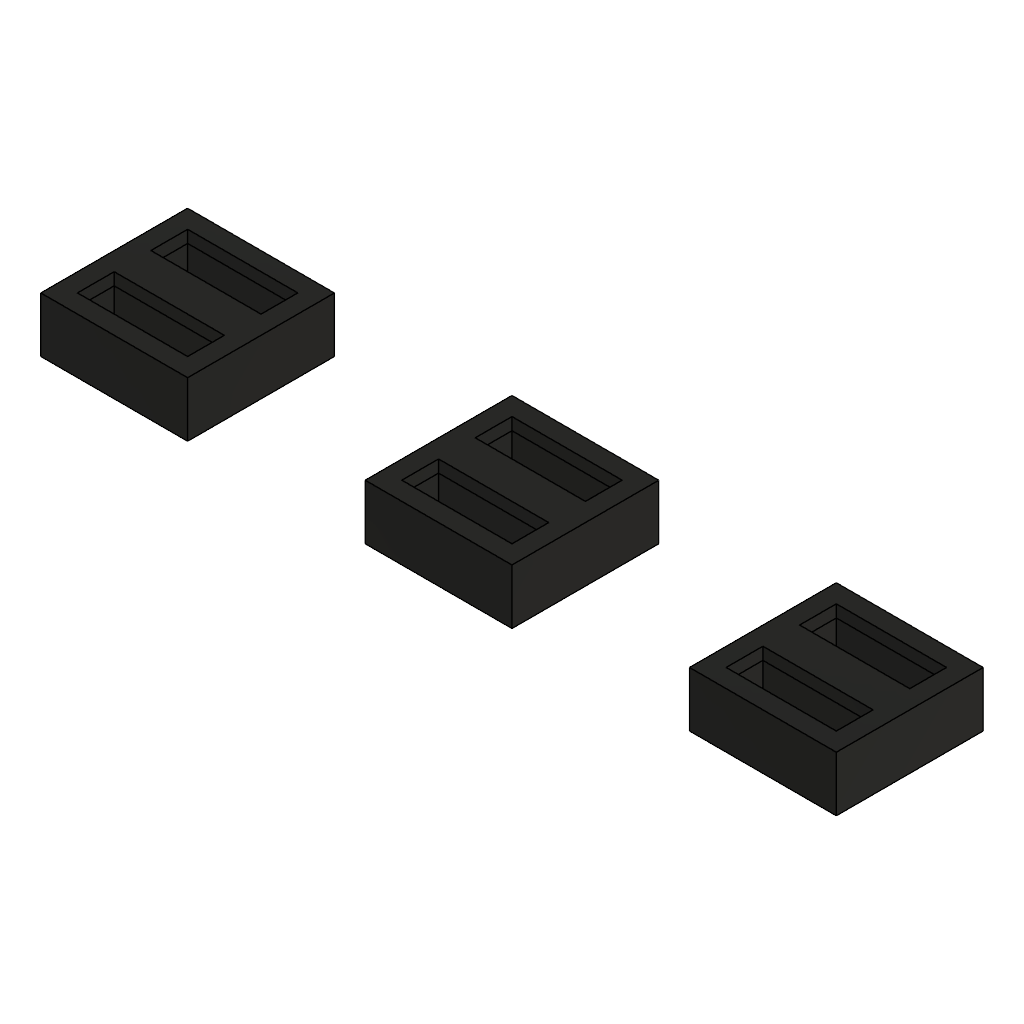
07-apu-illuminated-caps (Autodesk Fusion 360 design; units mm, degrees)
part number: 2026-10-09-16-49-26-867
Autodesk Fusion 360 part; units mm, degrees
sketch "MASTER SW illuminated cap footprint" plane through (0, 0, 0) normal (0, 0, 1) x (1, 0, 0)
  line L0 (25, 33) -> (49, 33)
  line L1 (49, 33) -> (49, 57)
  line L2 (49, 57) -> (25, 57)
  line L3 (25, 57) -> (25, 33)
extrude "MASTER SW illuminated cap" add sketch "MASTER SW illuminated cap footprint" along normal blind 9 makes body 1
ref_plane "WorkPlane1" through (0, 0, 7) normal (0, 0, 1) x (1, 0, 0)
sketch "MASTER SW optical bay ON" plane through (0, 0, 7) normal (0, 0, 1) x (1, 0, 0)
  line L0 (27, 35) -> (47, 35)
  line L1 (47, 35) -> (47, 43)
  line L2 (47, 43) -> (27, 43)
  line L3 (27, 43) -> (27, 35)
extrude "MASTER SW optical bay ON cut" cut sketch "MASTER SW optical bay ON" against normal blind 5 bodies 1
ref_plane "WorkPlane2" through (0, 0, 9) normal (0, 0, 1) x (1, 0, 0)
sketch "MASTER SW light window ON" plane through (0, 0, 9) normal (0, 0, 1) x (1, 0, 0)
  line L0 (28, 36) -> (46, 36)
  line L1 (46, 36) -> (46, 42)
  line L2 (46, 42) -> (28, 42)
  line L3 (28, 42) -> (28, 36)
extrude "MASTER SW light window ON cut" cut sketch "MASTER SW light window ON" against normal blind 2 bodies 1
ref_plane "WorkPlane3" through (0, 0, 2) normal (0, 0, 1) x (1, 0, 0)
sketch "MASTER SW LED bore ON" plane through (0, 0, 2) normal (0, 0, 1) x (1, 0, 0)
  circle A0 centre (37, 39) radius 1.6
extrude "MASTER SW LED bore ON cut" cut sketch "MASTER SW LED bore ON" against normal blind 2 bodies 1
ref_plane "WorkPlane4" through (0, 0, 7) normal (0, 0, 1) x (1, 0, 0)
sketch "MASTER SW optical bay FAULT" plane through (0, 0, 7) normal (0, 0, 1) x (1, 0, 0)
  line L0 (27, 47) -> (47, 47)
  line L1 (47, 47) -> (47, 55)
  line L2 (47, 55) -> (27, 55)
  line L3 (27, 55) -> (27, 47)
extrude "MASTER SW optical bay FAULT cut" cut sketch "MASTER SW optical bay FAULT" against normal blind 5 bodies 1
ref_plane "WorkPlane5" through (0, 0, 9) normal (0, 0, 1) x (1, 0, 0)
sketch "MASTER SW light window FAULT" plane through (0, 0, 9) normal (0, 0, 1) x (1, 0, 0)
  line L0 (28, 48) -> (46, 48)
  line L1 (46, 48) -> (46, 54)
  line L2 (46, 54) -> (28, 54)
  line L3 (28, 54) -> (28, 48)
extrude "MASTER SW light window FAULT cut" cut sketch "MASTER SW light window FAULT" against normal blind 2 bodies 1
ref_plane "WorkPlane6" through (0, 0, 2) normal (0, 0, 1) x (1, 0, 0)
sketch "MASTER SW LED bore FAULT" plane through (0, 0, 2) normal (0, 0, 1) x (1, 0, 0)
  circle A0 centre (37, 51) radius 1.6
extrude "MASTER SW LED bore FAULT cut" cut sketch "MASTER SW LED bore FAULT" against normal blind 2 bodies 1
ref_plane "WorkPlane7" through (0, 0, 2) normal (0, 0, 1) x (1, 0, 0)
sketch "MASTER SW actuator pilot" plane through (0, 0, 2) normal (0, 0, 1) x (1, 0, 0)
  circle A0 centre (37, 45) radius 1.2
extrude "MASTER SW actuator pilot cut" cut sketch "MASTER SW actuator pilot" against normal blind 2 bodies 1
sketch "START illuminated cap footprint" plane through (0, 0, 0) normal (0, 0, 1) x (1, 0, 0)
  line L0 (78, 33) -> (102, 33)
  line L1 (102, 33) -> (102, 57)
  line L2 (102, 57) -> (78, 57)
  line L3 (78, 57) -> (78, 33)
extrude "START illuminated cap" add sketch "START illuminated cap footprint" along normal blind 9 separate body makes body 2
ref_plane "WorkPlane8" through (0, 0, 7) normal (0, 0, 1) x (1, 0, 0)
sketch "START optical bay ON" plane through (0, 0, 7) normal (0, 0, 1) x (1, 0, 0)
  line L0 (80, 35) -> (100, 35)
  line L1 (100, 35) -> (100, 43)
  line L2 (100, 43) -> (80, 43)
  line L3 (80, 43) -> (80, 35)
extrude "START optical bay ON cut" cut sketch "START optical bay ON" against normal blind 5 bodies 2
ref_plane "WorkPlane9" through (0, 0, 9) normal (0, 0, 1) x (1, 0, 0)
sketch "START light window ON" plane through (0, 0, 9) normal (0, 0, 1) x (1, 0, 0)
  line L0 (81, 36) -> (99, 36)
  line L1 (99, 36) -> (99, 42)
  line L2 (99, 42) -> (81, 42)
  line L3 (81, 42) -> (81, 36)
extrude "START light window ON cut" cut sketch "START light window ON" against normal blind 2 bodies 2
ref_plane "WorkPlane10" through (0, 0, 2) normal (0, 0, 1) x (1, 0, 0)
sketch "START LED bore ON" plane through (0, 0, 2) normal (0, 0, 1) x (1, 0, 0)
  circle A0 centre (90, 39) radius 1.6
extrude "START LED bore ON cut" cut sketch "START LED bore ON" against normal blind 2 bodies 2
ref_plane "WorkPlane11" through (0, 0, 7) normal (0, 0, 1) x (1, 0, 0)
sketch "START optical bay AVAIL" plane through (0, 0, 7) normal (0, 0, 1) x (1, 0, 0)
  line L0 (80, 47) -> (100, 47)
  line L1 (100, 47) -> (100, 55)
  line L2 (100, 55) -> (80, 55)
  line L3 (80, 55) -> (80, 47)
extrude "START optical bay AVAIL cut" cut sketch "START optical bay AVAIL" against normal blind 5 bodies 2
ref_plane "WorkPlane12" through (0, 0, 9) normal (0, 0, 1) x (1, 0, 0)
sketch "START light window AVAIL" plane through (0, 0, 9) normal (0, 0, 1) x (1, 0, 0)
  line L0 (81, 48) -> (99, 48)
  line L1 (99, 48) -> (99, 54)
  line L2 (99, 54) -> (81, 54)
  line L3 (81, 54) -> (81, 48)
extrude "START light window AVAIL cut" cut sketch "START light window AVAIL" against normal blind 2 bodies 2
ref_plane "WorkPlane13" through (0, 0, 2) normal (0, 0, 1) x (1, 0, 0)
sketch "START LED bore AVAIL" plane through (0, 0, 2) normal (0, 0, 1) x (1, 0, 0)
  circle A0 centre (90, 51) radius 1.6
extrude "START LED bore AVAIL cut" cut sketch "START LED bore AVAIL" against normal blind 2 bodies 2
ref_plane "WorkPlane14" through (0, 0, 2) normal (0, 0, 1) x (1, 0, 0)
sketch "START actuator pilot" plane through (0, 0, 2) normal (0, 0, 1) x (1, 0, 0)
  circle A0 centre (90, 45) radius 1.2
extrude "START actuator pilot cut" cut sketch "START actuator pilot" against normal blind 2 bodies 2
sketch "APU BLEED illuminated cap footprint" plane through (0, 0, 0) normal (0, 0, 1) x (1, 0, 0)
  line L0 (131, 33) -> (155, 33)
  line L1 (155, 33) -> (155, 57)
  line L2 (155, 57) -> (131, 57)
  line L3 (131, 57) -> (131, 33)
extrude "APU BLEED illuminated cap" add sketch "APU BLEED illuminated cap footprint" along normal blind 9 separate body makes body 3
ref_plane "WorkPlane15" through (0, 0, 7) normal (0, 0, 1) x (1, 0, 0)
sketch "APU BLEED optical bay ON" plane through (0, 0, 7) normal (0, 0, 1) x (1, 0, 0)
  line L0 (133, 35) -> (153, 35)
  line L1 (153, 35) -> (153, 43)
  line L2 (153, 43) -> (133, 43)
  line L3 (133, 43) -> (133, 35)
extrude "APU BLEED optical bay ON cut" cut sketch "APU BLEED optical bay ON" against normal blind 5 bodies 3
ref_plane "WorkPlane16" through (0, 0, 9) normal (0, 0, 1) x (1, 0, 0)
sketch "APU BLEED light window ON" plane through (0, 0, 9) normal (0, 0, 1) x (1, 0, 0)
  line L0 (134, 36) -> (152, 36)
  line L1 (152, 36) -> (152, 42)
  line L2 (152, 42) -> (134, 42)
  line L3 (134, 42) -> (134, 36)
extrude "APU BLEED light window ON cut" cut sketch "APU BLEED light window ON" against normal blind 2 bodies 3
ref_plane "WorkPlane17" through (0, 0, 2) normal (0, 0, 1) x (1, 0, 0)
sketch "APU BLEED LED bore ON" plane through (0, 0, 2) normal (0, 0, 1) x (1, 0, 0)
  circle A0 centre (143, 39) radius 1.6
extrude "APU BLEED LED bore ON cut" cut sketch "APU BLEED LED bore ON" against normal blind 2 bodies 3
ref_plane "WorkPlane18" through (0, 0, 7) normal (0, 0, 1) x (1, 0, 0)
sketch "APU BLEED optical bay FAULT" plane through (0, 0, 7) normal (0, 0, 1) x (1, 0, 0)
  line L0 (133, 47) -> (153, 47)
  line L1 (153, 47) -> (153, 55)
  line L2 (153, 55) -> (133, 55)
  line L3 (133, 55) -> (133, 47)
extrude "APU BLEED optical bay FAULT cut" cut sketch "APU BLEED optical bay FAULT" against normal blind 5 bodies 3
ref_plane "WorkPlane19" through (0, 0, 9) normal (0, 0, 1) x (1, 0, 0)
sketch "APU BLEED light window FAULT" plane through (0, 0, 9) normal (0, 0, 1) x (1, 0, 0)
  line L0 (134, 48) -> (152, 48)
  line L1 (152, 48) -> (152, 54)
  line L2 (152, 54) -> (134, 54)
  line L3 (134, 54) -> (134, 48)
extrude "APU BLEED light window FAULT cut" cut sketch "APU BLEED light window FAULT" against normal blind 2 bodies 3
ref_plane "WorkPlane20" through (0, 0, 2) normal (0, 0, 1) x (1, 0, 0)
sketch "APU BLEED LED bore FAULT" plane through (0, 0, 2) normal (0, 0, 1) x (1, 0, 0)
  circle A0 centre (143, 51) radius 1.6
extrude "APU BLEED LED bore FAULT cut" cut sketch "APU BLEED LED bore FAULT" against normal blind 2 bodies 3
ref_plane "WorkPlane21" through (0, 0, 2) normal (0, 0, 1) x (1, 0, 0)
sketch "APU BLEED actuator pilot" plane through (0, 0, 2) normal (0, 0, 1) x (1, 0, 0)
  circle A0 centre (143, 45) radius 1.2
extrude "APU BLEED actuator pilot cut" cut sketch "APU BLEED actuator pilot" against normal blind 2 bodies 3
named bodies: "MASTER SW illuminated cap", "START illuminated cap", "APU BLEED illuminated cap"
